Autodesk Fusion 360 part; units mm, degrees
(part 2 of 2)
sketch "Sketch6 (3)" plane through (0, 0, 13) normal (0, 0, -1) x (1, 0, 0) in component "Small_Drawer_PRINT v1 (2)"
  line L0 (0.5, 0) -> (31.3, 0)
  line L1 (31.3, 0) -> (31.3, 13)
  line L2 (31.3, 13) -> (0.5, 13)
  line L3 (0.5, 13) -> (0.5, 0)
  line L4 (0.5, 13) -> (31.3, 13)
  line L5 (31.3, 13) -> (31.3, 12.2)
  line L6 (31.3, 12.2) -> (0.5, 12.2)
  line L7 (0.5, 12.2) -> (0.5, 13)
  dimension "d37_2" = 0.8
  constraint horizontal L4
  constraint vertical L5
  constraint horizontal L6
  constraint vertical L7
  constraint coincident L2.end L3.start
  measures "d37_2" distance of L2.end L6.end
extrude "Extrude7'''" add sketch "Sketch6 (3)" along normal blind 13 contours L1 L2 L3 L4 L5 L6 L7 bodies 4 in component "Small_Drawer_PRINT v1 (2)"
sketch "Sketch8 (3)" plane through (0, 0, 13) normal (0, 0, -1) x (1, 0, 0) in component "Small_Drawer_PRINT v1 (2)"
  line L0 (31.3, 12.2) -> (0.5, 12.2)
  line L1 (0.5, 12.2) -> (0.5, 0)
  line L2 (0.5, 0) -> (31.3, 0)
  line L3 (31.3, 0) -> (31.3, 12.2)
  line L4 (1.3, 0) -> (0.5, 0)
  line L5 (0.5, 0) -> (0.5, 12.2)
  line L6 (0.5, 12.2) -> (1.3, 12.2)
  line L7 (1.3, 12.2) -> (1.3, 0)
  line L8 (31.3, 0) -> (30.5, 0)
  line L9 (30.5, 0) -> (30.5, 12.2)
  line L10 (30.5, 12.2) -> (31.3, 12.2)
  line L11 (31.3, 12.2) -> (31.3, 0)
  dimension "d45_2" = 0.8
  dimension "d46_2" = 0.8
  constraint horizontal L4
  constraint vertical L5
  constraint horizontal L6
  constraint vertical L7
  constraint coincident L0.end L1.start
  constraint coincident L2 L4.start
  constraint horizontal L8
  constraint vertical L9
  constraint horizontal L10
  constraint vertical L11
  constraint coincident L0 L9.end
  constraint coincident L2.end L3.start
  measures "d45_2" distance of L9.end L0.start
  measures "d46_2" distance of L0.end L6.end
extrude "Extrude9''" add sketch "Sketch8 (3)" along normal blind 13 contours L0 L2 L3 L8 L9 L10 L11 | L0 L1 L2 L4 L5 L6 L7 bodies 4 in component "Small_Drawer_PRINT v1 (2)"
fillet "Fillet2''" radius 4 2 edges at (15.9, -12.2, 13) (15.9, -13, 13.8) on bodies 4 in component "Small_Drawer_PRINT v1 (2)"
chamfer "Chamfer1''" distance 3 angle 45 1 edges at (15.9, 0, 13) on bodies 4 in component "Small_Drawer_PRINT v1 (2)"
fillet "Fillet3''" radius 2 6 edges at (31.3, -4.5, 13.8) (31.3, -11.8284, 12.6284) (31.3, -13, 4.9) (30.5, -5.6, 13) (30.5, -11.0284, 11.8284) (30.5, -12.2, 4.5) on bodies 4 in component "Small_Drawer_PRINT v1 (2)"
fillet "Fillet4''" radius 2 6 edges at (1.3, -12.2, 4.5) (1.3, -11.0284, 11.8284) (1.3, -5.6, 13) (0.5, -4.5, 13.8) (0.5, -11.8284, 12.6284) (0.5, -13, 4.9) on bodies 4 in component "Small_Drawer_PRINT v1 (2)"
sketch "Sketch1 (5)" plane through (0, 0, 0) normal (0, 0, 1) x (1, 0, 0) in component "Small_Drawer_PRINT v1 (3)"
  line L0 (0, 0) -> (31.8, 0)
  line L1 (31.8, 0) -> (31.8, 80)
  line L2 (31.8, 80) -> (0, 80)
  line L3 (0, 80) -> (0, 0)
  dimension "d1_4" = 31.8
  dimension "d2_4" = 80
  constraint horizontal L0
  constraint vertical L1
  constraint horizontal L2
  constraint vertical L3
  constraint coincident L0.start L3.end
  measures "d1_4" distance of L0.start L0.end
  measures "d2_4" distance of L0.end L1.end
extrude "Extrude1''''" add sketch "Sketch1 (5)" along normal blind 26.2 separate body makes body 5 in component "Small_Drawer_PRINT v1 (3)"
shell "Shell1'''" thickness 0.8 removed faces 1 at (10.6, 26.6667, 26.2) on bodies 5 in component "Small_Drawer_PRINT v1 (3)"
ref_plane "WorkPlane1" through (13.4, 40, 13.1) normal (1, 0, 0) x (0, 1, 0) in component "Small_Drawer_PRINT v1 (3)"
sketch "Sketch3 (5)" plane through (0, 80, 0) normal (0, 1, 0) x (-1, 0, 0) in component "Small_Drawer_PRINT v1 (3)"
  line L0 (-31.8, 0) -> (0, 0)
  line L1 (0, 0) -> (0, 26.2)
  line L2 (0, 26.2) -> (-31.8, 26.2)
  line L3 (-31.8, 26.2) -> (-31.8, 0)
  line L4 (-15.9, 26.2) -> (-15.9, 0) construction
  line L5 (-27.55, 27.45) -> (-27.55, 28.45)
  line L6 (-26.3, 29.7) -> (-23.3, 29.7)
  line L7 (-22.05, 28.45) -> (-22.05, 27.45)
  line L8 (-28.8, 26.2) -> (-20.8, 26.2)
  arc A0 (-28.8, 26.2) -> (-27.55, 27.45) centre (-28.8, 27.45) ccw
  arc A1 (-26.3, 29.7) -> (-27.55, 28.45) centre (-26.3, 28.45) ccw
  arc A2 (-22.05, 28.45) -> (-23.3, 29.7) centre (-23.3, 28.45) ccw
  arc A3 (-22.05, 27.45) -> (-20.8, 26.2) centre (-20.8, 27.45) ccw
  arc A4 (-4.25, 28.45) -> (-5.5, 29.7) centre (-5.5, 28.45) ccw
  line L9 (-5.5, 29.7) -> (-8.5, 29.7)
  arc A5 (-11, 26.2) -> (-9.75, 27.45) centre (-11, 27.45) ccw
  arc A6 (-4.25, 27.45) -> (-3, 26.2) centre (-3, 27.45) ccw
  line L10 (-4.25, 27.45) -> (-4.25, 28.45)
  line L11 (-3, 26.2) -> (-11, 26.2)
  arc A7 (-8.5, 29.7) -> (-9.75, 28.45) centre (-8.5, 28.45) ccw
  line L12 (-9.75, 28.45) -> (-9.75, 27.45)
  point P0 (-24.8, 29.7)
  point P1 (-7, 29.7)
  dimension "d18_3" = 7
  dimension "d19_4" = 3.5
  dimension "d20_3" = 5.5
  dimension "d21_4" = 1.25
  constraint midpoint L2 L4.start
  constraint perpendicular L2 L4
  constraint coincident L0 L4.end
  constraint horizontal L6
  constraint tangent L6 A1
  constraint tangent L5 A1
  constraint tangent L5 A0
  constraint tangent L6 A2
  constraint tangent L7 A2
  constraint tangent L7 A3
  constraint tangent L8 A3
  constraint tangent L8 A0
  constraint equal A0 A1
  constraint equal A1 A2
  constraint equal A2 A3
  constraint collinear L2 L8
  constraint vertical L7
  constraint vertical L5
  constraint midpoint L6 P0
  constraint symmetric L4 L5.start A6.start
  constraint symmetric L4 L5.end A4.start
  constraint symmetric L4 L6.start A4.end
  constraint symmetric L4 L6.end L9.end
  constraint symmetric L4 L7.start A7.end
  constraint symmetric L4 L7.end A5.end
  constraint symmetric L4 L8.start A6.end
  constraint symmetric L4 L8.end A5.start
  constraint symmetric L4 P0 P1
  constraint symmetric L4 A0 A6
  constraint symmetric L4 A1 A4
  constraint symmetric L4 A2 A7
  constraint symmetric L4 A3 A5
  measures "d18_3" distance of L3 P0
  measures "d19_4" distance of L6 L8
  measures "d20_3" distance of L5 L7
  measures "d21_4" radius of A0
extrude "Extrude3''''" add sketch "Sketch3 (5)" against normal blind 0.8 contours L2 L5 L6 L7 L8 A0 A1 A2 A3 | L2 A4 L9 A5 A6 L10 L11 A7 L12 bodies 5 in component "Small_Drawer_PRINT v1 (3)"
sketch "Sketch4 (5)" plane through (31.8, 0, 0) normal (1, 0, 0) x (0, 1, 0) in component "Small_Drawer_PRINT v1 (3)"
  line L0 (0, 0) -> (80, 0)
  line L1 (80, 0) -> (80, 26.2)
  line L2 (80, 26.2) -> (0, 26.2)
  line L3 (0, 26.2) -> (0, 0)
  line L4 (0.9071, 26.2) -> (10.1071, 17)
  line L5 (0.9071, 26.2) -> (7.8528, 26.2) construction
  line L6 (10.1071, 17) -> (69.7311, 17)
  line L7 (69.7311, 17) -> (78.9311, 26.2)
  line L8 (78.9311, 26.2) -> (0.9071, 26.2)
  dimension "d24_4" = 45
  dimension "d25_4" = 135
  dimension "d26_4" = 17
  constraint horizontal L5
  constraint coincident L2 L4.start
  constraint horizontal L6
  constraint coincident L2 L7.end
  measures "d24_4" angle of L4 L5
  measures "d25_4" angle of L6 L7
  measures "d26_4" distance of L0 L6
extrude "Extrude4''''" cut sketch "Sketch4 (5)" against normal blind 31.8 contours L2 L4 L6 L7 L8 bodies 5 in component "Small_Drawer_PRINT v1 (3)"
extrude "Extrude5''''" add 1 faces at (17.5333, 79.2, 9.2667) along direction (0, -1, 0) blind 0.4 on bodies 5 bodies 5 in component "Small_Drawer_PRINT v1 (3)"
sketch "Sketch5 (5)" plane through (0, 0, 0) normal (0, -1, 0) x (1, 0, 0) in component "Small_Drawer_PRINT v1 (3)"
  line L0 (0, 0) -> (31.8, 0)
  line L1 (31.8, 0) -> (31.8, 26.2)
  line L2 (31.8, 26.2) -> (0, 26.2)
  line L3 (0, 26.2) -> (0, 0)
  line L4 (0.5, 13.8) -> (31.3, 13.8)
  line L5 (31.3, 13.8) -> (31.3, 13)
  line L6 (31.3, 13) -> (0.5, 13)
  line L7 (0.5, 13) -> (0.5, 13.8)
  dimension "d31_4" = 0.5
  dimension "d32_4" = 0.5
  dimension "d33_4" = 0.8
  dimension "d34_4" = 13
  constraint horizontal L4
  constraint vertical L5
  constraint horizontal L6
  constraint vertical L7
  measures "d31_4" distance of L3 L7
  measures "d32_4" distance of L1 L5
  measures "d33_4" distance of L4 L6
  measures "d34_4" distance of L0 L6
extrude "Extrude6''''" add sketch "Sketch5 (5)" along normal blind 13 contours L4 L5 L6 L7 bodies 5 in component "Small_Drawer_PRINT v1 (3)"
sketch "Sketch6 (4)" plane through (0, 0, 13) normal (0, 0, -1) x (1, 0, 0) in component "Small_Drawer_PRINT v1 (3)"
  line L0 (0.5, 0) -> (31.3, 0)
  line L1 (31.3, 0) -> (31.3, 13)
  line L2 (31.3, 13) -> (0.5, 13)
  line L3 (0.5, 13) -> (0.5, 0)
  line L4 (0.5, 13) -> (31.3, 13)
  line L5 (31.3, 13) -> (31.3, 12.2)
  line L6 (31.3, 12.2) -> (0.5, 12.2)
  line L7 (0.5, 12.2) -> (0.5, 13)
  dimension "d37_3" = 0.8
  constraint horizontal L4
  constraint vertical L5
  constraint horizontal L6
  constraint vertical L7
  constraint coincident L2.end L3.start
  measures "d37_3" distance of L2.end L6.end
extrude "Extrude7''''" add sketch "Sketch6 (4)" along normal blind 13 contours L1 L2 L3 L4 L5 L6 L7 bodies 5 in component "Small_Drawer_PRINT v1 (3)"
sketch "Sketch8 (4)" plane through (0, 0, 13) normal (0, 0, -1) x (1, 0, 0) in component "Small_Drawer_PRINT v1 (3)"
  line L0 (31.3, 12.2) -> (0.5, 12.2)
  line L1 (0.5, 12.2) -> (0.5, 0)
  line L2 (0.5, 0) -> (31.3, 0)
  line L3 (31.3, 0) -> (31.3, 12.2)
  line L4 (1.3, 0) -> (0.5, 0)
  line L5 (0.5, 0) -> (0.5, 12.2)
  line L6 (0.5, 12.2) -> (1.3, 12.2)
  line L7 (1.3, 12.2) -> (1.3, 0)
  line L8 (31.3, 0) -> (30.5, 0)
  line L9 (30.5, 0) -> (30.5, 12.2)
  line L10 (30.5, 12.2) -> (31.3, 12.2)
  line L11 (31.3, 12.2) -> (31.3, 0)
  dimension "d45_3" = 0.8
  dimension "d46_3" = 0.8
  constraint horizontal L4
  constraint vertical L5
  constraint horizontal L6
  constraint vertical L7
  constraint coincident L0.end L1.start
  constraint coincident L2 L4.start
  constraint horizontal L8
  constraint vertical L9
  constraint horizontal L10
  constraint vertical L11
  constraint coincident L0 L9.end
  constraint coincident L2.end L3.start
  measures "d45_3" distance of L9.end L0.start
  measures "d46_3" distance of L0.end L6.end
extrude "Extrude9'''" add sketch "Sketch8 (4)" along normal blind 13 contours L0 L2 L3 L8 L9 L10 L11 | L0 L1 L2 L4 L5 L6 L7 bodies 5 in component "Small_Drawer_PRINT v1 (3)"
fillet "Fillet2'''" radius 4 2 edges at (15.9, -12.2, 13) (15.9, -13, 13.8) on bodies 5 in component "Small_Drawer_PRINT v1 (3)"
chamfer "Chamfer1'''" distance 3 angle 45 1 edges at (15.9, 0, 13) on bodies 5 in component "Small_Drawer_PRINT v1 (3)"
fillet "Fillet3'''" radius 2 6 edges at (31.3, -4.5, 13.8) (31.3, -11.8284, 12.6284) (31.3, -13, 4.9) (30.5, -5.6, 13) (30.5, -11.0284, 11.8284) (30.5, -12.2, 4.5) on bodies 5 in component "Small_Drawer_PRINT v1 (3)"
fillet "Fillet4'''" radius 2 6 edges at (1.3, -12.2, 4.5) (1.3, -11.0284, 11.8284) (1.3, -5.6, 13) (0.5, -4.5, 13.8) (0.5, -11.8284, 12.6284) (0.5, -13, 4.9) on bodies 5 in component "Small_Drawer_PRINT v1 (3)"
sketch "Sketch1 (6)" plane through (0, 0, 0) normal (0, 0, 1) x (1, 0, 0) in component "Small_Drawer_PRINT v1 (4)"
  line L0 (0, 0) -> (31.8, 0)
  line L1 (31.8, 0) -> (31.8, 80)
  line L2 (31.8, 80) -> (0, 80)
  line L3 (0, 80) -> (0, 0)
  dimension "d1_5" = 31.8
  dimension "d2_5" = 80
  constraint horizontal L0
  constraint vertical L1
  constraint horizontal L2
  constraint vertical L3
  constraint coincident L0.start L3.end
  measures "d1_5" distance of L0.start L0.end
  measures "d2_5" distance of L0.end L1.end
extrude "Extrude1'''''" add sketch "Sketch1 (6)" along normal blind 26.2 separate body makes body 6 in component "Small_Drawer_PRINT v1 (4)"
shell "Shell1''''" thickness 0.8 removed faces 1 at (10.6, 26.6667, 26.2) on bodies 6 in component "Small_Drawer_PRINT v1 (4)"
ref_plane "WorkPlane1" through (13.4, 40, 13.1) normal (1, 0, 0) x (0, 1, 0) in component "Small_Drawer_PRINT v1 (4)"
sketch "Sketch3 (6)" plane through (0, 80, 0) normal (0, 1, 0) x (-1, 0, 0) in component "Small_Drawer_PRINT v1 (4)"
  line L0 (-31.8, 0) -> (0, 0)
  line L1 (0, 0) -> (0, 26.2)
  line L2 (0, 26.2) -> (-31.8, 26.2)
  line L3 (-31.8, 26.2) -> (-31.8, 0)
  line L4 (-15.9, 26.2) -> (-15.9, 0) construction
  line L5 (-27.55, 27.45) -> (-27.55, 28.45)
  line L6 (-26.3, 29.7) -> (-23.3, 29.7)
  line L7 (-22.05, 28.45) -> (-22.05, 27.45)
  line L8 (-28.8, 26.2) -> (-20.8, 26.2)
  arc A0 (-28.8, 26.2) -> (-27.55, 27.45) centre (-28.8, 27.45) ccw
  arc A1 (-26.3, 29.7) -> (-27.55, 28.45) centre (-26.3, 28.45) ccw
  arc A2 (-22.05, 28.45) -> (-23.3, 29.7) centre (-23.3, 28.45) ccw
  arc A3 (-22.05, 27.45) -> (-20.8, 26.2) centre (-20.8, 27.45) ccw
  arc A4 (-4.25, 28.45) -> (-5.5, 29.7) centre (-5.5, 28.45) ccw
  line L9 (-5.5, 29.7) -> (-8.5, 29.7)
  arc A5 (-11, 26.2) -> (-9.75, 27.45) centre (-11, 27.45) ccw
  arc A6 (-4.25, 27.45) -> (-3, 26.2) centre (-3, 27.45) ccw
  line L10 (-4.25, 27.45) -> (-4.25, 28.45)
  line L11 (-3, 26.2) -> (-11, 26.2)
  arc A7 (-8.5, 29.7) -> (-9.75, 28.45) centre (-8.5, 28.45) ccw
  line L12 (-9.75, 28.45) -> (-9.75, 27.45)
  point P0 (-24.8, 29.7)
  point P1 (-7, 29.7)
  dimension "d18_4" = 7
  dimension "d19_5" = 3.5
  dimension "d20_4" = 5.5
  dimension "d21_5" = 1.25
  constraint midpoint L2 L4.start
  constraint perpendicular L2 L4
  constraint coincident L0 L4.end
  constraint horizontal L6
  constraint tangent L6 A1
  constraint tangent L5 A1
  constraint tangent L5 A0
  constraint tangent L6 A2
  constraint tangent L7 A2
  constraint tangent L7 A3
  constraint tangent L8 A3
  constraint tangent L8 A0
  constraint equal A0 A1
  constraint equal A1 A2
  constraint equal A2 A3
  constraint collinear L2 L8
  constraint vertical L7
  constraint vertical L5
  constraint midpoint L6 P0
  constraint symmetric L4 L5.start A6.start
  constraint symmetric L4 L5.end A4.start
  constraint symmetric L4 L6.start A4.end
  constraint symmetric L4 L6.end L9.end
  constraint symmetric L4 L7.start A7.end
  constraint symmetric L4 L7.end A5.end
  constraint symmetric L4 L8.start A6.end
  constraint symmetric L4 L8.end A5.start
  constraint symmetric L4 P0 P1
  constraint symmetric L4 A0 A6
  constraint symmetric L4 A1 A4
  constraint symmetric L4 A2 A7
  constraint symmetric L4 A3 A5
  measures "d18_4" distance of L3 P0
  measures "d19_5" distance of L6 L8
  measures "d20_4" distance of L5 L7
  measures "d21_5" radius of A0
extrude "Extrude3'''''" add sketch "Sketch3 (6)" against normal blind 0.8 contours L2 L5 L6 L7 L8 A0 A1 A2 A3 | L2 A4 L9 A5 A6 L10 L11 A7 L12 bodies 6 in component "Small_Drawer_PRINT v1 (4)"
sketch "Sketch4 (6)" plane through (31.8, 0, 0) normal (1, 0, 0) x (0, 1, 0) in component "Small_Drawer_PRINT v1 (4)"
  line L0 (0, 0) -> (80, 0)
  line L1 (80, 0) -> (80, 26.2)
  line L2 (80, 26.2) -> (0, 26.2)
  line L3 (0, 26.2) -> (0, 0)
  line L4 (0.9071, 26.2) -> (10.1071, 17)
  line L5 (0.9071, 26.2) -> (7.8528, 26.2) construction
  line L6 (10.1071, 17) -> (69.7311, 17)
  line L7 (69.7311, 17) -> (78.9311, 26.2)
  line L8 (78.9311, 26.2) -> (0.9071, 26.2)
  dimension "d24_5" = 45
  dimension "d25_5" = 135
  dimension "d26_5" = 17
  constraint horizontal L5
  constraint coincident L2 L4.start
  constraint horizontal L6
  constraint coincident L2 L7.end
  measures "d24_5" angle of L4 L5
  measures "d25_5" angle of L6 L7
  measures "d26_5" distance of L0 L6
extrude "Extrude4'''''" cut sketch "Sketch4 (6)" against normal blind 31.8 contours L2 L4 L6 L7 L8 bodies 6 in component "Small_Drawer_PRINT v1 (4)"
extrude "Extrude5'''''" add 1 faces at (17.5333, 79.2, 9.2667) along direction (0, -1, 0) blind 0.4 on bodies 6 bodies 6 in component "Small_Drawer_PRINT v1 (4)"
sketch "Sketch5 (6)" plane through (0, 0, 0) normal (0, -1, 0) x (1, 0, 0) in component "Small_Drawer_PRINT v1 (4)"
  line L0 (0, 0) -> (31.8, 0)
  line L1 (31.8, 0) -> (31.8, 26.2)
  line L2 (31.8, 26.2) -> (0, 26.2)
  line L3 (0, 26.2) -> (0, 0)
  line L4 (0.5, 13.8) -> (31.3, 13.8)
  line L5 (31.3, 13.8) -> (31.3, 13)
  line L6 (31.3, 13) -> (0.5, 13)
  line L7 (0.5, 13) -> (0.5, 13.8)
  dimension "d31_5" = 0.5
  dimension "d32_5" = 0.5
  dimension "d33_5" = 0.8
  dimension "d34_5" = 13
  constraint horizontal L4
  constraint vertical L5
  constraint horizontal L6
  constraint vertical L7
  measures "d31_5" distance of L3 L7
  measures "d32_5" distance of L1 L5
  measures "d33_5" distance of L4 L6
  measures "d34_5" distance of L0 L6
extrude "Extrude6'''''" add sketch "Sketch5 (6)" along normal blind 13 contours L4 L5 L6 L7 bodies 6 in component "Small_Drawer_PRINT v1 (4)"
sketch "Sketch6 (5)" plane through (0, 0, 13) normal (0, 0, -1) x (1, 0, 0) in component "Small_Drawer_PRINT v1 (4)"
  line L0 (0.5, 0) -> (31.3, 0)
  line L1 (31.3, 0) -> (31.3, 13)
  line L2 (31.3, 13) -> (0.5, 13)
  line L3 (0.5, 13) -> (0.5, 0)
  line L4 (0.5, 13) -> (31.3, 13)
  line L5 (31.3, 13) -> (31.3, 12.2)
  line L6 (31.3, 12.2) -> (0.5, 12.2)
  line L7 (0.5, 12.2) -> (0.5, 13)
  dimension "d37_4" = 0.8
  constraint horizontal L4
  constraint vertical L5
  constraint horizontal L6
  constraint vertical L7
  constraint coincident L2.end L3.start
  measures "d37_4" distance of L2.end L6.end
extrude "Extrude7'''''" add sketch "Sketch6 (5)" along normal blind 13 contours L1 L2 L3 L4 L5 L6 L7 bodies 6 in component "Small_Drawer_PRINT v1 (4)"
sketch "Sketch8 (5)" plane through (0, 0, 13) normal (0, 0, -1) x (1, 0, 0) in component "Small_Drawer_PRINT v1 (4)"
  line L0 (31.3, 12.2) -> (0.5, 12.2)
  line L1 (0.5, 12.2) -> (0.5, 0)
  line L2 (0.5, 0) -> (31.3, 0)
  line L3 (31.3, 0) -> (31.3, 12.2)
  line L4 (1.3, 0) -> (0.5, 0)
  line L5 (0.5, 0) -> (0.5, 12.2)
  line L6 (0.5, 12.2) -> (1.3, 12.2)
  line L7 (1.3, 12.2) -> (1.3, 0)
  line L8 (31.3, 0) -> (30.5, 0)
  line L9 (30.5, 0) -> (30.5, 12.2)
  line L10 (30.5, 12.2) -> (31.3, 12.2)
  line L11 (31.3, 12.2) -> (31.3, 0)
  dimension "d45_4" = 0.8
  dimension "d46_4" = 0.8
  constraint horizontal L4
  constraint vertical L5
  constraint horizontal L6
  constraint vertical L7
  constraint coincident L0.end L1.start
  constraint coincident L2 L4.start
  constraint horizontal L8
  constraint vertical L9
  constraint horizontal L10
  constraint vertical L11
  constraint coincident L0 L9.end
  constraint coincident L2.end L3.start
  measures "d45_4" distance of L9.end L0.start
  measures "d46_4" distance of L0.end L6.end
extrude "Extrude9''''" add sketch "Sketch8 (5)" along normal blind 13 contours L0 L2 L3 L8 L9 L10 L11 | L0 L1 L2 L4 L5 L6 L7 bodies 6 in component "Small_Drawer_PRINT v1 (4)"
fillet "Fillet2''''" radius 4 2 edges at (15.9, -12.2, 13) (15.9, -13, 13.8) on bodies 6 in component "Small_Drawer_PRINT v1 (4)"
chamfer "Chamfer1''''" distance 3 angle 45 1 edges at (15.9, 0, 13) on bodies 6 in component "Small_Drawer_PRINT v1 (4)"
fillet "Fillet3''''" radius 2 6 edges at (31.3, -4.5, 13.8) (31.3, -11.8284, 12.6284) (31.3, -13, 4.9) (30.5, -5.6, 13) (30.5, -11.0284, 11.8284) (30.5, -12.2, 4.5) on bodies 6 in component "Small_Drawer_PRINT v1 (4)"
fillet "Fillet4''''" radius 2 6 edges at (1.3, -12.2, 4.5) (1.3, -11.0284, 11.8284) (1.3, -5.6, 13) (0.5, -4.5, 13.8) (0.5, -11.8284, 12.6284) (0.5, -13, 4.9) on bodies 6 in component "Small_Drawer_PRINT v1 (4)"
sketch "Sketch1 (7)" plane through (0, 0, 0) normal (0, 0, 1) x (1, 0, 0) in component "Small_Drawer_PRINT v1 (5)"
  line L0 (0, 0) -> (31.8, 0)
  line L1 (31.8, 0) -> (31.8, 80)
  line L2 (31.8, 80) -> (0, 80)
  line L3 (0, 80) -> (0, 0)
  dimension "d1_6" = 31.8
  dimension "d2_6" = 80
  constraint horizontal L0
  constraint vertical L1
  constraint horizontal L2
  constraint vertical L3
  constraint coincident L0.start L3.end
  measures "d1_6" distance of L0.start L0.end
  measures "d2_6" distance of L0.end L1.end
extrude "Extrude1''''''" add sketch "Sketch1 (7)" along normal blind 26.2 separate body makes body 7 in component "Small_Drawer_PRINT v1 (5)"
shell "Shell1'''''" thickness 0.8 removed faces 1 at (10.6, 26.6667, 26.2) on bodies 7 in component "Small_Drawer_PRINT v1 (5)"
ref_plane "WorkPlane1" through (13.4, 40, 13.1) normal (1, 0, 0) x (0, 1, 0) in component "Small_Drawer_PRINT v1 (5)"
sketch "Sketch3 (7)" plane through (0, 80, 0) normal (0, 1, 0) x (-1, 0, 0) in component "Small_Drawer_PRINT v1 (5)"
  line L0 (-31.8, 0) -> (0, 0)
  line L1 (0, 0) -> (0, 26.2)
  line L2 (0, 26.2) -> (-31.8, 26.2)
  line L3 (-31.8, 26.2) -> (-31.8, 0)
  line L4 (-15.9, 26.2) -> (-15.9, 0) construction
  line L5 (-27.55, 27.45) -> (-27.55, 28.45)
  line L6 (-26.3, 29.7) -> (-23.3, 29.7)
  line L7 (-22.05, 28.45) -> (-22.05, 27.45)
  line L8 (-28.8, 26.2) -> (-20.8, 26.2)
  arc A0 (-28.8, 26.2) -> (-27.55, 27.45) centre (-28.8, 27.45) ccw
  arc A1 (-26.3, 29.7) -> (-27.55, 28.45) centre (-26.3, 28.45) ccw
  arc A2 (-22.05, 28.45) -> (-23.3, 29.7) centre (-23.3, 28.45) ccw
  arc A3 (-22.05, 27.45) -> (-20.8, 26.2) centre (-20.8, 27.45) ccw
  arc A4 (-4.25, 28.45) -> (-5.5, 29.7) centre (-5.5, 28.45) ccw
  line L9 (-5.5, 29.7) -> (-8.5, 29.7)
  arc A5 (-11, 26.2) -> (-9.75, 27.45) centre (-11, 27.45) ccw
  arc A6 (-4.25, 27.45) -> (-3, 26.2) centre (-3, 27.45) ccw
  line L10 (-4.25, 27.45) -> (-4.25, 28.45)
  line L11 (-3, 26.2) -> (-11, 26.2)
  arc A7 (-8.5, 29.7) -> (-9.75, 28.45) centre (-8.5, 28.45) ccw
  line L12 (-9.75, 28.45) -> (-9.75, 27.45)
  point P0 (-24.8, 29.7)
  point P1 (-7, 29.7)
  dimension "d18_5" = 7
  dimension "d19_6" = 3.5
  dimension "d20_5" = 5.5
  dimension "d21_6" = 1.25
  constraint midpoint L2 L4.start
  constraint perpendicular L2 L4
  constraint coincident L0 L4.end
  constraint horizontal L6
  constraint tangent L6 A1
  constraint tangent L5 A1
  constraint tangent L5 A0
  constraint tangent L6 A2
  constraint tangent L7 A2
  constraint tangent L7 A3
  constraint tangent L8 A3
  constraint tangent L8 A0
  constraint equal A0 A1
  constraint equal A1 A2
  constraint equal A2 A3
  constraint collinear L2 L8
  constraint vertical L7
  constraint vertical L5
  constraint midpoint L6 P0
  constraint symmetric L4 L5.start A6.start
  constraint symmetric L4 L5.end A4.start
  constraint symmetric L4 L6.start A4.end
  constraint symmetric L4 L6.end L9.end
  constraint symmetric L4 L7.start A7.end
  constraint symmetric L4 L7.end A5.end
  constraint symmetric L4 L8.start A6.end
  constraint symmetric L4 L8.end A5.start
  constraint symmetric L4 P0 P1
  constraint symmetric L4 A0 A6
  constraint symmetric L4 A1 A4
  constraint symmetric L4 A2 A7
  constraint symmetric L4 A3 A5
  measures "d18_5" distance of L3 P0
  measures "d19_6" distance of L6 L8
  measures "d20_5" distance of L5 L7
  measures "d21_6" radius of A0
extrude "Extrude3''''''" add sketch "Sketch3 (7)" against normal blind 0.8 contours L2 L5 L6 L7 L8 A0 A1 A2 A3 | L2 A4 L9 A5 A6 L10 L11 A7 L12 bodies 7 in component "Small_Drawer_PRINT v1 (5)"
sketch "Sketch4 (7)" plane through (31.8, 0, 0) normal (1, 0, 0) x (0, 1, 0) in component "Small_Drawer_PRINT v1 (5)"
  line L0 (0, 0) -> (80, 0)
  line L1 (80, 0) -> (80, 26.2)
  line L2 (80, 26.2) -> (0, 26.2)
  line L3 (0, 26.2) -> (0, 0)
  line L4 (0.9071, 26.2) -> (10.1071, 17)
  line L5 (0.9071, 26.2) -> (7.8528, 26.2) construction
  line L6 (10.1071, 17) -> (69.7311, 17)
  line L7 (69.7311, 17) -> (78.9311, 26.2)
  line L8 (78.9311, 26.2) -> (0.9071, 26.2)
  dimension "d24_6" = 45
  dimension "d25_6" = 135
  dimension "d26_6" = 17
  constraint horizontal L5
  constraint coincident L2 L4.start
  constraint horizontal L6
  constraint coincident L2 L7.end
  measures "d24_6" angle of L4 L5
  measures "d25_6" angle of L6 L7
  measures "d26_6" distance of L0 L6
extrude "Extrude4''''''" cut sketch "Sketch4 (7)" against normal blind 31.8 contours L2 L4 L6 L7 L8 bodies 7 in component "Small_Drawer_PRINT v1 (5)"
extrude "Extrude5''''''" add 1 faces at (17.5333, 79.2, 9.2667) along direction (0, -1, 0) blind 0.4 on bodies 7 bodies 7 in component "Small_Drawer_PRINT v1 (5)"
sketch "Sketch5 (7)" plane through (0, 0, 0) normal (0, -1, 0) x (1, 0, 0) in component "Small_Drawer_PRINT v1 (5)"
  line L0 (0, 0) -> (31.8, 0)
  line L1 (31.8, 0) -> (31.8, 26.2)
  line L2 (31.8, 26.2) -> (0, 26.2)
  line L3 (0, 26.2) -> (0, 0)
  line L4 (0.5, 13.8) -> (31.3, 13.8)
  line L5 (31.3, 13.8) -> (31.3, 13)
  line L6 (31.3, 13) -> (0.5, 13)
  line L7 (0.5, 13) -> (0.5, 13.8)
  dimension "d31_6" = 0.5
  dimension "d32_6" = 0.5
  dimension "d33_6" = 0.8
  dimension "d34_6" = 13
  constraint horizontal L4
  constraint vertical L5
  constraint horizontal L6
  constraint vertical L7
  measures "d31_6" distance of L3 L7
  measures "d32_6" distance of L1 L5
  measures "d33_6" distance of L4 L6
  measures "d34_6" distance of L0 L6
extrude "Extrude6''''''" add sketch "Sketch5 (7)" along normal blind 13 contours L4 L5 L6 L7 bodies 7 in component "Small_Drawer_PRINT v1 (5)"
sketch "Sketch6 (6)" plane through (0, 0, 13) normal (0, 0, -1) x (1, 0, 0) in component "Small_Drawer_PRINT v1 (5)"
  line L0 (0.5, 0) -> (31.3, 0)
  line L1 (31.3, 0) -> (31.3, 13)
  line L2 (31.3, 13) -> (0.5, 13)
  line L3 (0.5, 13) -> (0.5, 0)
  line L4 (0.5, 13) -> (31.3, 13)
  line L5 (31.3, 13) -> (31.3, 12.2)
  line L6 (31.3, 12.2) -> (0.5, 12.2)
  line L7 (0.5, 12.2) -> (0.5, 13)
  dimension "d37_5" = 0.8
  constraint horizontal L4
  constraint vertical L5
  constraint horizontal L6
  constraint vertical L7
  constraint coincident L2.end L3.start
  measures "d37_5" distance of L2.end L6.end
extrude "Extrude7''''''" add sketch "Sketch6 (6)" along normal blind 13 contours L1 L2 L3 L4 L5 L6 L7 bodies 7 in component "Small_Drawer_PRINT v1 (5)"
sketch "Sketch8 (6)" plane through (0, 0, 13) normal (0, 0, -1) x (1, 0, 0) in component "Small_Drawer_PRINT v1 (5)"
  line L0 (31.3, 12.2) -> (0.5, 12.2)
  line L1 (0.5, 12.2) -> (0.5, 0)
  line L2 (0.5, 0) -> (31.3, 0)
  line L3 (31.3, 0) -> (31.3, 12.2)
  line L4 (1.3, 0) -> (0.5, 0)
  line L5 (0.5, 0) -> (0.5, 12.2)
  line L6 (0.5, 12.2) -> (1.3, 12.2)
  line L7 (1.3, 12.2) -> (1.3, 0)
  line L8 (31.3, 0) -> (30.5, 0)
  line L9 (30.5, 0) -> (30.5, 12.2)
  line L10 (30.5, 12.2) -> (31.3, 12.2)
  line L11 (31.3, 12.2) -> (31.3, 0)
  dimension "d45_5" = 0.8
  dimension "d46_5" = 0.8
  constraint horizontal L4
  constraint vertical L5
  constraint horizontal L6
  constraint vertical L7
  constraint coincident L0.end L1.start
  constraint coincident L2 L4.start
  constraint horizontal L8
  constraint vertical L9
  constraint horizontal L10
  constraint vertical L11
  constraint coincident L0 L9.end
  constraint coincident L2.end L3.start
  measures "d45_5" distance of L9.end L0.start
  measures "d46_5" distance of L0.end L6.end
extrude "Extrude9'''''" add sketch "Sketch8 (6)" along normal blind 13 contours L0 L2 L3 L8 L9 L10 L11 | L0 L1 L2 L4 L5 L6 L7 bodies 7 in component "Small_Drawer_PRINT v1 (5)"
fillet "Fillet2'''''" radius 4 2 edges at (15.9, -12.2, 13) (15.9, -13, 13.8) on bodies 7 in component "Small_Drawer_PRINT v1 (5)"
chamfer "Chamfer1'''''" distance 3 angle 45 1 edges at (15.9, 0, 13) on bodies 7 in component "Small_Drawer_PRINT v1 (5)"
fillet "Fillet3'''''" radius 2 6 edges at (31.3, -4.5, 13.8) (31.3, -11.8284, 12.6284) (31.3, -13, 4.9) (30.5, -5.6, 13) (30.5, -11.0284, 11.8284) (30.5, -12.2, 4.5) on bodies 7 in component "Small_Drawer_PRINT v1 (5)"
fillet "Fillet4'''''" radius 2 6 edges at (1.3, -12.2, 4.5) (1.3, -11.0284, 11.8284) (1.3, -5.6, 13) (0.5, -4.5, 13.8) (0.5, -11.8284, 12.6284) (0.5, -13, 4.9) on bodies 7 in component "Small_Drawer_PRINT v1 (5)"
sketch "Sketch1 (8)" plane through (0, 0, 0) normal (0, 0, 1) x (1, 0, 0) in component "Small_Drawer_PRINT v1 (6)"
  line L0 (0, 0) -> (31.8, 0)
  line L1 (31.8, 0) -> (31.8, 80)
  line L2 (31.8, 80) -> (0, 80)
  line L3 (0, 80) -> (0, 0)
  dimension "d1_7" = 31.8
  dimension "d2_7" = 80
  constraint horizontal L0
  constraint vertical L1
  constraint horizontal L2
  constraint vertical L3
  constraint coincident L0.start L3.end
  measures "d1_7" distance of L0.start L0.end
  measures "d2_7" distance of L0.end L1.end
extrude "Extrude1'''''''" add sketch "Sketch1 (8)" along normal blind 26.2 separate body makes body 8 in component "Small_Drawer_PRINT v1 (6)"
shell "Shell1''''''" thickness 0.8 removed faces 1 at (10.6, 26.6667, 26.2) on bodies 8 in component "Small_Drawer_PRINT v1 (6)"
ref_plane "WorkPlane1" through (13.4, 40, 13.1) normal (1, 0, 0) x (0, 1, 0) in component "Small_Drawer_PRINT v1 (6)"
sketch "Sketch3 (8)" plane through (0, 80, 0) normal (0, 1, 0) x (-1, 0, 0) in component "Small_Drawer_PRINT v1 (6)"
  line L0 (-31.8, 0) -> (0, 0)
  line L1 (0, 0) -> (0, 26.2)
  line L2 (0, 26.2) -> (-31.8, 26.2)
  line L3 (-31.8, 26.2) -> (-31.8, 0)
  line L4 (-15.9, 26.2) -> (-15.9, 0) construction
  line L5 (-27.55, 27.45) -> (-27.55, 28.45)
  line L6 (-26.3, 29.7) -> (-23.3, 29.7)
  line L7 (-22.05, 28.45) -> (-22.05, 27.45)
  line L8 (-28.8, 26.2) -> (-20.8, 26.2)
  arc A0 (-28.8, 26.2) -> (-27.55, 27.45) centre (-28.8, 27.45) ccw
  arc A1 (-26.3, 29.7) -> (-27.55, 28.45) centre (-26.3, 28.45) ccw
  arc A2 (-22.05, 28.45) -> (-23.3, 29.7) centre (-23.3, 28.45) ccw
  arc A3 (-22.05, 27.45) -> (-20.8, 26.2) centre (-20.8, 27.45) ccw
  arc A4 (-4.25, 28.45) -> (-5.5, 29.7) centre (-5.5, 28.45) ccw
  line L9 (-5.5, 29.7) -> (-8.5, 29.7)
  arc A5 (-11, 26.2) -> (-9.75, 27.45) centre (-11, 27.45) ccw
  arc A6 (-4.25, 27.45) -> (-3, 26.2) centre (-3, 27.45) ccw
  line L10 (-4.25, 27.45) -> (-4.25, 28.45)
  line L11 (-3, 26.2) -> (-11, 26.2)
  arc A7 (-8.5, 29.7) -> (-9.75, 28.45) centre (-8.5, 28.45) ccw
  line L12 (-9.75, 28.45) -> (-9.75, 27.45)
  point P0 (-24.8, 29.7)
  point P1 (-7, 29.7)
  dimension "d18_6" = 7
  dimension "d19_7" = 3.5
  dimension "d20_6" = 5.5
  dimension "d21_7" = 1.25
  constraint midpoint L2 L4.start
  constraint perpendicular L2 L4
  constraint coincident L0 L4.end
  constraint horizontal L6
  constraint tangent L6 A1
  constraint tangent L5 A1
  constraint tangent L5 A0
  constraint tangent L6 A2
  constraint tangent L7 A2
  constraint tangent L7 A3
  constraint tangent L8 A3
  constraint tangent L8 A0
  constraint equal A0 A1
  constraint equal A1 A2
  constraint equal A2 A3
  constraint collinear L2 L8
  constraint vertical L7
  constraint vertical L5
  constraint midpoint L6 P0
  constraint symmetric L4 L5.start A6.start
  constraint symmetric L4 L5.end A4.start
  constraint symmetric L4 L6.start A4.end
  constraint symmetric L4 L6.end L9.end
  constraint symmetric L4 L7.start A7.end
  constraint symmetric L4 L7.end A5.end
  constraint symmetric L4 L8.start A6.end
  constraint symmetric L4 L8.end A5.start
  constraint symmetric L4 P0 P1
  constraint symmetric L4 A0 A6
  constraint symmetric L4 A1 A4
  constraint symmetric L4 A2 A7
  constraint symmetric L4 A3 A5
  measures "d18_6" distance of L3 P0
  measures "d19_7" distance of L6 L8
  measures "d20_6" distance of L5 L7
  measures "d21_7" radius of A0
extrude "Extrude3'''''''" add sketch "Sketch3 (8)" against normal blind 0.8 contours L2 L5 L6 L7 L8 A0 A1 A2 A3 | L2 A4 L9 A5 A6 L10 L11 A7 L12 bodies 8 in component "Small_Drawer_PRINT v1 (6)"
sketch "Sketch4 (8)" plane through (31.8, 0, 0) normal (1, 0, 0) x (0, 1, 0) in component "Small_Drawer_PRINT v1 (6)"
  line L0 (0, 0) -> (80, 0)
  line L1 (80, 0) -> (80, 26.2)
  line L2 (80, 26.2) -> (0, 26.2)
  line L3 (0, 26.2) -> (0, 0)
  line L4 (0.9071, 26.2) -> (10.1071, 17)
  line L5 (0.9071, 26.2) -> (7.8528, 26.2) construction
  line L6 (10.1071, 17) -> (69.7311, 17)
  line L7 (69.7311, 17) -> (78.9311, 26.2)
  line L8 (78.9311, 26.2) -> (0.9071, 26.2)
  dimension "d24_7" = 45
  dimension "d25_7" = 135
  dimension "d26_7" = 17
  constraint horizontal L5
  constraint coincident L2 L4.start
  constraint horizontal L6
  constraint coincident L2 L7.end
  measures "d24_7" angle of L4 L5
  measures "d25_7" angle of L6 L7
  measures "d26_7" distance of L0 L6
extrude "Extrude4'''''''" cut sketch "Sketch4 (8)" against normal blind 31.8 contours L2 L4 L6 L7 L8 bodies 8 in component "Small_Drawer_PRINT v1 (6)"
extrude "Extrude5'''''''" add 1 faces at (17.5333, 79.2, 9.2667) along direction (0, -1, 0) blind 0.4 on bodies 8 bodies 8 in component "Small_Drawer_PRINT v1 (6)"
sketch "Sketch5 (8)" plane through (0, 0, 0) normal (0, -1, 0) x (1, 0, 0) in component "Small_Drawer_PRINT v1 (6)"
  line L0 (0, 0) -> (31.8, 0)
  line L1 (31.8, 0) -> (31.8, 26.2)
  line L2 (31.8, 26.2) -> (0, 26.2)
  line L3 (0, 26.2) -> (0, 0)
  line L4 (0.5, 13.8) -> (31.3, 13.8)
  line L5 (31.3, 13.8) -> (31.3, 13)
  line L6 (31.3, 13) -> (0.5, 13)
  line L7 (0.5, 13) -> (0.5, 13.8)
  dimension "d31_7" = 0.5
  dimension "d32_7" = 0.5
  dimension "d33_7" = 0.8
  dimension "d34_7" = 13
  constraint horizontal L4
  constraint vertical L5
  constraint horizontal L6
  constraint vertical L7
  measures "d31_7" distance of L3 L7
  measures "d32_7" distance of L1 L5
  measures "d33_7" distance of L4 L6
  measures "d34_7" distance of L0 L6
extrude "Extrude6'''''''" add sketch "Sketch5 (8)" along normal blind 13 contours L4 L5 L6 L7 bodies 8 in component "Small_Drawer_PRINT v1 (6)"
sketch "Sketch6 (7)" plane through (0, 0, 13) normal (0, 0, -1) x (1, 0, 0) in component "Small_Drawer_PRINT v1 (6)"
  line L0 (0.5, 0) -> (31.3, 0)
  line L1 (31.3, 0) -> (31.3, 13)
  line L2 (31.3, 13) -> (0.5, 13)
  line L3 (0.5, 13) -> (0.5, 0)
  line L4 (0.5, 13) -> (31.3, 13)
  line L5 (31.3, 13) -> (31.3, 12.2)
  line L6 (31.3, 12.2) -> (0.5, 12.2)
  line L7 (0.5, 12.2) -> (0.5, 13)
  dimension "d37_6" = 0.8
  constraint horizontal L4
  constraint vertical L5
  constraint horizontal L6
  constraint vertical L7
  constraint coincident L2.end L3.start
  measures "d37_6" distance of L2.end L6.end
extrude "Extrude7'''''''" add sketch "Sketch6 (7)" along normal blind 13 contours L1 L2 L3 L4 L5 L6 L7 bodies 8 in component "Small_Drawer_PRINT v1 (6)"
sketch "Sketch8 (7)" plane through (0, 0, 13) normal (0, 0, -1) x (1, 0, 0) in component "Small_Drawer_PRINT v1 (6)"
  line L0 (31.3, 12.2) -> (0.5, 12.2)
  line L1 (0.5, 12.2) -> (0.5, 0)
  line L2 (0.5, 0) -> (31.3, 0)
  line L3 (31.3, 0) -> (31.3, 12.2)
  line L4 (1.3, 0) -> (0.5, 0)
  line L5 (0.5, 0) -> (0.5, 12.2)
  line L6 (0.5, 12.2) -> (1.3, 12.2)
  line L7 (1.3, 12.2) -> (1.3, 0)
  line L8 (31.3, 0) -> (30.5, 0)
  line L9 (30.5, 0) -> (30.5, 12.2)
  line L10 (30.5, 12.2) -> (31.3, 12.2)
  line L11 (31.3, 12.2) -> (31.3, 0)
  dimension "d45_6" = 0.8
  dimension "d46_6" = 0.8
  constraint horizontal L4
  constraint vertical L5
  constraint horizontal L6
  constraint vertical L7
  constraint coincident L0.end L1.start
  constraint coincident L2 L4.start
  constraint horizontal L8
  constraint vertical L9
  constraint horizontal L10
  constraint vertical L11
  constraint coincident L0 L9.end
  constraint coincident L2.end L3.start
  measures "d45_6" distance of L9.end L0.start
  measures "d46_6" distance of L0.end L6.end
extrude "Extrude9''''''" add sketch "Sketch8 (7)" along normal blind 13 contours L0 L2 L3 L8 L9 L10 L11 | L0 L1 L2 L4 L5 L6 L7 bodies 8 in component "Small_Drawer_PRINT v1 (6)"
fillet "Fillet2''''''" radius 4 2 edges at (15.9, -12.2, 13) (15.9, -13, 13.8) on bodies 8 in component "Small_Drawer_PRINT v1 (6)"
chamfer "Chamfer1''''''" distance 3 angle 45 1 edges at (15.9, 0, 13) on bodies 8 in component "Small_Drawer_PRINT v1 (6)"
fillet "Fillet3''''''" radius 2 6 edges at (31.3, -4.5, 13.8) (31.3, -11.8284, 12.6284) (31.3, -13, 4.9) (30.5, -5.6, 13) (30.5, -11.0284, 11.8284) (30.5, -12.2, 4.5) on bodies 8 in component "Small_Drawer_PRINT v1 (6)"
fillet "Fillet4''''''" radius 2 6 edges at (1.3, -12.2, 4.5) (1.3, -11.0284, 11.8284) (1.3, -5.6, 13) (0.5, -4.5, 13.8) (0.5, -11.8284, 12.6284) (0.5, -13, 4.9) on bodies 8 in component "Small_Drawer_PRINT v1 (6)"
sketch "Sketch6 (8)" plane through (0, 0, 0) normal (0, -1, 0) x (1, 0, 0)
  line L0 (99.4, 28.2) -> (99.4, 1.2)
  line L1 (99.4, 1.2) -> (67.2, 1.2)
  line L2 (67.2, 1.2) -> (67.2, 28.2)
  line L3 (67.2, 28.2) -> (99.4, 28.2)
  line L4 (199.2, 1.2) -> (199.2, 28.2)
  line L5 (199.2, 28.2) -> (231.4, 28.2)
  line L6 (231.4, 28.2) -> (231.4, 1.2)
  line L7 (231.4, 1.2) -> (199.2, 1.2)
  line L8 (132.4, 28.2) -> (132.4, 1.2)
  line L9 (132.4, 1.2) -> (100.2, 1.2)
  line L10 (100.2, 1.2) -> (100.2, 28.2)
  line L11 (100.2, 28.2) -> (132.4, 28.2)
  line L12 (66.4, 28.2) -> (66.4, 1.2)
  line L13 (66.4, 1.2) -> (34.2, 1.2)
  line L14 (34.2, 1.2) -> (34.2, 28.2)
  line L15 (34.2, 28.2) -> (66.4, 28.2)
  line L16 (166.2, 1.2) -> (166.2, 28.2)
  line L17 (166.2, 28.2) -> (198.4, 28.2)
  line L18 (198.4, 28.2) -> (198.4, 1.2)
  line L19 (198.4, 1.2) -> (166.2, 1.2)
  line L20 (165.4, 28.2) -> (165.4, 1.2)
  line L21 (165.4, 1.2) -> (133.2, 1.2)
  line L22 (133.2, 1.2) -> (133.2, 28.2)
  line L23 (133.2, 28.2) -> (165.4, 28.2)
  line L24 (33.4, 28.2) -> (33.4, 1.2)
  line L25 (33.4, 1.2) -> (1.2, 1.2)
  line L26 (1.2, 1.2) -> (1.2, 28.2)
  line L27 (1.2, 28.2) -> (33.4, 28.2)
  line L28 (0, 0) -> (232.6, 0)
  line L29 (232.6, 0) -> (232.6, 38.2)
  line L30 (232.6, 38.2) -> (0, 38.2)
  line L31 (0, 38.2) -> (0, 0)
  line L32 (0, 38.2) -> (232.6, 38.2)
  line L33 (232.6, 38.2) -> (232.6, 28.2)
  line L34 (232.6, 28.2) -> (0, 28.2)
  line L35 (0, 28.2) -> (0, 38.2)
  dimension "d269" = 10
  constraint horizontal L32
  constraint vertical L33
  constraint horizontal L34
  constraint vertical L35
  constraint coincident L30.end L31.start
  measures "d269" distance of L30.end L34.end
extrude "Extrude9'''''''" add sketch "Sketch6 (8)" along normal blind 2 separate body contours L3 L5 L11 L15 L17 L23 L27 L29 L30 L31 L32 L33 L34 L35 makes body 9
sketch "Sketch7" plane through (0, -2, 0) normal (0, -1, 0) x (1, 0, 0)
  line L0 (0, 28.2) -> (232.6, 28.2)
  line L1 (232.6, 28.2) -> (232.6, 38.2)
  line L2 (232.6, 38.2) -> (0, 38.2)
  line L3 (0, 38.2) -> (0, 28.2)
  line L4 (15, 35.7) -> (20, 35.7)
  line L5 (20, 35.7) -> (20, 30.7)
  line L6 (20, 30.7) -> (15, 30.7)
  line L7 (15, 30.7) -> (15, 35.7)
  line L8 (48, 35.7) -> (53, 35.7)
  line L9 (53, 35.7) -> (53, 30.7)
  line L10 (53, 30.7) -> (48, 30.7)
  line L11 (48, 30.7) -> (48, 35.7)
  line L12 (81, 35.7) -> (86, 35.7)
  line L13 (86, 35.7) -> (86, 30.7)
  line L14 (86, 30.7) -> (81, 30.7)
  line L15 (81, 30.7) -> (81, 35.7)
  line L16 (114, 35.7) -> (119, 35.7)
  line L17 (119, 35.7) -> (119, 30.7)
  line L18 (119, 30.7) -> (114, 30.7)
  line L19 (114, 30.7) -> (114, 35.7)
  line L20 (147, 35.7) -> (152, 35.7)
  line L21 (152, 35.7) -> (152, 30.7)
  line L22 (152, 30.7) -> (147, 30.7)
  line L23 (147, 30.7) -> (147, 35.7)
  line L24 (180, 35.7) -> (185, 35.7)
  line L25 (185, 35.7) -> (185, 30.7)
  line L26 (185, 30.7) -> (180, 30.7)
  line L27 (180, 30.7) -> (180, 35.7)
  line L28 (213, 35.7) -> (218, 35.7)
  line L29 (218, 35.7) -> (218, 30.7)
  line L30 (218, 30.7) -> (213, 30.7)
  line L31 (213, 30.7) -> (213, 35.7)
  dimension "d272" = 5
  dimension "d273" = 5
  dimension "d274" = 5
  dimension "d275" = 5
  dimension "d276" = 28
  dimension "d277" = 15
  dimension "d278" = 5
  dimension "d279" = 5
  dimension "d280" = 28
  dimension "d281" = 5
  dimension "d282" = 5
  dimension "d283" = 28
  dimension "d284" = 5
  dimension "d285" = 5
  dimension "d286" = 28
  dimension "d287" = 5
  dimension "d288" = 5
  dimension "d289" = 28
  dimension "d290" = 5
  dimension "d291" = 5
  dimension "d292" = 28
  dimension "d293" = 2.5
  dimension "d294" = 2.5
  dimension "d295" = 2.5
  dimension "d296" = 2.5
  dimension "d297" = 2.5
  dimension "d298" = 2.5
  dimension "d299" = 2.5
  constraint horizontal L4
  constraint vertical L5
  constraint horizontal L6
  constraint vertical L7
  constraint horizontal L8
  constraint vertical L9
  constraint horizontal L10
  constraint vertical L11
  constraint horizontal L12
  constraint vertical L13
  constraint horizontal L14
  constraint vertical L15
  constraint horizontal L16
  constraint vertical L17
  constraint horizontal L18
  constraint vertical L19
  constraint horizontal L20
  constraint vertical L21
  constraint horizontal L22
  constraint vertical L23
  constraint horizontal L24
  constraint vertical L25
  constraint horizontal L26
  constraint vertical L27
  constraint horizontal L28
  constraint vertical L29
  constraint horizontal L30
  constraint vertical L31
  measures "d272" distance of L4.start L4.end
  measures "d273" distance of L4.start L6.end
  measures "d274" distance of L8.start L8.end
  measures "d275" distance of L8.start L10.end
  measures "d276" distance of L5 L11
  measures "d277" distance of L3 L7
  measures "d278" distance of L12.start L12.end
  measures "d279" distance of L12.start L14.end
  measures "d280" distance of L9 L15
  measures "d281" distance of L16.start L16.end
  measures "d282" distance of L16.start L18.end
  measures "d283" distance of L13 L19
  measures "d284" distance of L20.start L20.end
  measures "d285" distance of L20.start L22.end
  measures "d286" distance of L17 L23
  measures "d287" distance of L24.start L24.end
  measures "d288" distance of L24.start L26.end
  measures "d289" distance of L21 L27
  measures "d290" distance of L28.start L28.end
  measures "d291" distance of L28.start L30.end
  measures "d292" distance of L25 L31
  measures "d293" distance of L2 L4
  measures "d294" distance of L2 L8
  measures "d295" distance of L2 L12
  measures "d296" distance of L2 L16
  measures "d297" distance of L2 L20
  measures "d298" distance of L2 L24
  measures "d299" distance of L2 L28
extrude "Extrude10" add sketch "Sketch7" along normal blind 2 contours L4 L5 L6 L7 | L8 L9 L10 L11 | L12 L13 L14 L15 | L16 L17 L18 L19 | L20 L21 L22 L23 | L24 L25 L26 L27 | L28 L29 L30 L31 bodies 9
component "Small_Drawer_PRINT v1" placed x (1, 0, 0) y (0, 1, 0) z (0, 0, 1) at (1.4, 0.4, 1.2)
component "Small_Drawer_PRINT v1 (1)" placed x (1, 0, 0) y (0, 1, 0) z (0, 0, 1) at (34.6, 0.4, 1.2)
component "Small_Drawer_PRINT v1 (2)" placed x (1, 0, 0) y (0, 1, 0) z (0, 0, 1) at (67.2, 0.4, 1.2)
component "Small_Drawer_PRINT v1 (3)" placed x (1, 0, 0) y (0, 1, 0) z (0, 0, 1) at (100.4, 0.1105, 1.35)
component "Small_Drawer_PRINT v1 (4)" placed x (1, 0, 0) y (0, 1, 0) z (0, 0, 1) at (133.4, 0.4, 1.2)
component "Small_Drawer_PRINT v1 (5)" placed x (1, 0, 0) y (0, 1, 0) z (0, 0, 1) at (166.4, 0.4, 1.2)
component "Small_Drawer_PRINT v1 (6)" placed x (1, 0, 0) y (0, 1, 0) z (0, 0, 1) at (199.4, 0.4, 1.2)
